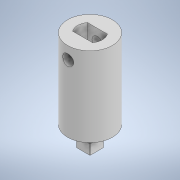
# Autodesk Inventor part: axv2
Saved by Autodesk Inventor 2022.6 (Build 266554000, 554)
## iProperties
Created: 2026-10-28
Part Number: axv2
Material: Generic
Document SubType Name: Modeling
Designer: Dragos Macovei
Density: 1 g/cm^3
Appearance: Default
Author: Dragos Macovei
Autodesk Inventor part; units mm, degrees
ref_plane "YZ Plane" through (0, 0, 0) normal (1, 0, 0) x (0, 1, 0)
ref_plane "XZ Plane" through (0, 0, 0) normal (0, 1, 0) x (-1, 0, 0)
ref_plane "XY Plane" through (0, 0, 0) normal (0, 0, 1) x (1, 0, 0)
sketch "Sketch1" plane through (0, 0, 0) normal (0, 1, 0) x (-1, 0, 0)
  circle A0 centre (0, 0) radius 4.5
  dimension "d0" = 9
  constraints: 1 centre point, 1 coincident
  measures "d0" diameter of A0
extrude "Extrusion1" add sketch "Sketch1" along normal blind 20
sketch "Sketch2" plane through (0, 20, 0) normal (0, 1, 0) x (1, 0, 0)
  circle A0 centre (0, 0) radius 2.5
  dimension "d3" = 5
  constraints: 1 centre point, 1 coincident
  measures "d3" diameter of A0
extrude "Extrusion2" cut sketch "Sketch2" against normal blind 5
sketch "Sketch3" plane through (0, 20, 0) normal (0, 1, 0) x (1, 0, 0)
  line L0 (-2.5, -1.5) -> (2.5, -1.5)
  line L1 (2.5, -1.5) -> (2.5, 1.5)
  line L2 (2.5, 1.5) -> (-2.5, 1.5)
  line L3 (-2.5, 1.5) -> (-2.5, -1.5)
  circle A0 centre (0, 0) radius 2.5 projected
  circle A1 centre (0, 0) radius 2.5 projected
  circle A2 centre (0, 0) radius 4.5 projected
  point P0 (2, -1.5)
  point P1 (-2, -1.5)
  point P2 (-2, 1.5)
  point P3 (2, 1.5)
  dimension "d6" = 2.5
  dimension "d7" = 2.5
  dimension "d8" = 1.5
  dimension "d9" = 1.5
  constraints: 8 end point, 2 parallel, 1 horizontal, 1 perpendicular
  measures "d6" distance from line of point (0, 0) L3
  measures "d7" distance from line of L1 point (0, 0)
  measures "d8" distance from line of point (0, 0) L0
  measures "d9" distance from line of point (0, 0) L2
extrude "Extrusion3" add sketch "Sketch3" against normal blind 5 contours L0 A0 | A0 L2
sketch "Sketch4" plane through (2, 20, 1.5) normal (0, 0, -1) x (-1, 0, 0)
  line L0 (6.5, 0) -> (-2.5, 0) projected
  line L1 (6.5, -20) -> (-2.5, -20) projected
  line L2 (4, -5) -> (4, 0) projected
  line L3 (0, 0) -> (0, -5) projected
  line L4 (0, -5) -> (4, -5) projected
  circle A0 centre (2, -2.5) radius 1.1
  point P0 (2, -20)
  dimension "d12" = 2.2
  constraints: 1 centre point
  measures "d12" diameter of A0
extrude "Extrusion4" cut sketch "Sketch4" along normal through all both and the other way through all contours A0
sketch "Sketch5" plane through (0, 0, 0) normal (0, -1, 0) x (1, 0, 0)
  line L0 (-1.4, -1.4) -> (1.4, -1.4)
  line L1 (1.4, -1.4) -> (1.4, 1.4)
  line L2 (1.4, 1.4) -> (-1.4, 1.4)
  line L3 (-1.4, 1.4) -> (-1.4, -1.4)
  circle A0 centre (0, 0) radius 4.5 projected
  point P0 (0, -1.4)
  point P1 (1.4, 0)
  dimension "d15" = 2.8
  dimension "d16" = 2.8
  dimension "d17" = 1.4
  dimension "d18" = 1.4
  constraints: 8 end point, 2 midpoint, 2 parallel, 1 horizontal, 1 perpendicular
  measures "d15" distance between parallel lines of L0 L2
  measures "d16" distance between parallel lines of L1 L3
  measures "d17" distance of point (0, 0) point (0, -1.4)
  measures "d18" distance of point (1.4, 0) point (0, 0)
extrude "Extrusion5" cut sketch "Sketch5" against normal blind 4
fillet "Fillet1" radius 0.1 4 edges at (-1.4, 2, -1.4) (-1.4, 2, 1.4) (1.4, 2, -1.4) (1.4, 2, 1.4)
fillet "Fillet2" radius 2 8 edges at (-1.3707, 4, -1.3707) (0, 4, -1.4) (1.3707, 4, -1.3707) (1.4, 4, 0) (1.3707, 4, 1.3707) (0, 4, 1.4) (-1.3707, 4, 1.3707) (-1.4, 4, 0) curvature continuous yes
sketch "Sketch6" plane through (0, 0, 0) normal (0, -1, 0) x (1, 0, 0)
  circle A0 centre (0, 0) radius 0.7
  dimension "d25" = 1.4
  constraints: 1 centre point, 1 coincident
  measures "d25" diameter of A0
extrude "Extrusion6" cut sketch "Sketch6" against normal through all
equation "\"d7\" = d6"
equation "\"d16\" = d15"
equation "\"d17\" = 0.5 * d15"
equation "\"d18\" = 0.5 * d16"
body "Solid1"
